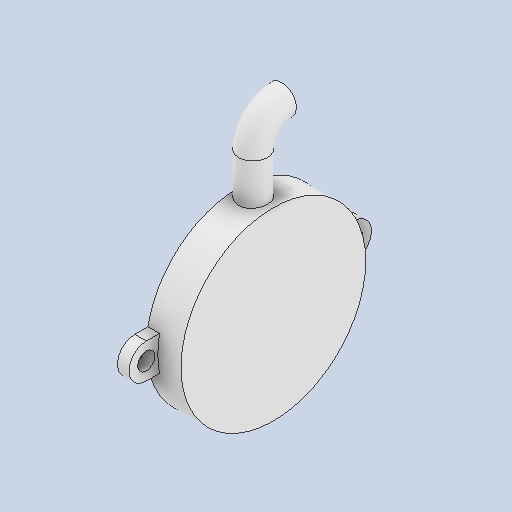
# Autodesk Inventor part: cylinder_head
Saved by Autodesk Inventor 2026.1 (Build 301233020, 233B)
## iProperties
Created: 2025-12-09
Part Number: cylinder_head
Material: Plastica ABS
Document SubType Name: Modeling
Designer: maxbu
Density: 1.06 g/cm^3
Appearance: Liscia - Bianco
Mass: 1.64306 g
Surface Area: 32.0135 cm^2
Volume: 1.55006 cm^3
Author: maxbu
Autodesk Inventor part; units mm, degrees
sketch "Schizzo1" plane through (0, 0, 0) normal (1, 0, 0) x (0, 1, 0)
  circle A0 centre (0, 0) radius 16
  circle A1 centre (0, 0) radius 15
  dimension "d0" = 32
  dimension "d1" = 30
  constraints: 2 centre point, 2 coincident
  measures "d0" diameter of A0
  measures "d1" diameter of A1
extrude "Estrusione1" add sketch "Schizzo1" along normal blind 5
sketch "Schizzo2" plane through (0, 0, 0) normal (1, 0, 0) x (0, 1, 0)
  circle A0 centre (0, -18) radius 1.5
  arc A1 (-3, -18) -> (3, -18) centre (0, -18) ccw
  line L0 (3, -18) -> (3, -15.7162)
  line L1 (-3, -18) -> (-3, -15.7162)
  circle A2 centre (0, 0) radius 16 projected
  line L2 (0, -18) -> (0, 0) construction
  line L3 (0, 0) -> (16, 0) construction
  circle A3 centre (0, 18) radius 1.5
  arc A4 (3, 18) -> (-3, 18) centre (0, 18) ccw
  line L4 (3, 18) -> (3, 15.7162)
  line L5 (-3, 18) -> (-3, 15.7162)
  dimension "d4" = 3
  dimension "d5" = 3
  dimension "d32" = 18
  constraints: 12 end point, 7 point on circle, 6 symmetric about line, 4 centre point, 3 coincident, 3 vertical, 2 tangent, 1 horizontal, 2 other
  measures "d4" radius of A1
  measures "d5" diameter of A0
  measures "d32" distance of point (0, 0) A0.centre
extrude "Estrusione2" add sketch "Schizzo2" along normal blind 2 contours L1 A2 L0 A1 | L5 A4 L4 A2
sketch "Schizzo5" plane through (5, 0, 0) normal (1, 0, 0) x (0, 0, -1)
  circle A0 centre (0, 0) radius 16 projected
extrude "Estrusione4" add sketch "Schizzo5" along normal blind 1
ref_plane "Piano di lavoro1" through (0, 20, 0) normal (0, 1, 0) x (-1, 0, 0)
sketch "Schizzo6" plane through (0, 20, 0) normal (0, 1, 0) x (-1, 0, 0)
  line L0 (0, 15.7162) -> (0, -15.7162) projected
  circle A0 centre (-2.5, 0) radius 2.5
  line L1 (-5, -15) -> (-5, 15) projected
  line L2 (0, 0) -> (-2.5, 0) construction
  line L3 (-2.5, 0) -> (-5, 0) construction
  dimension "d22" = 5
  constraints: 4 end point, 1 centre point, 1 collinear, 1 horizontal, 1 midpoint
  measures "d22" diameter of A0
extrude "Estrusione5" add sketch "Schizzo6" against normal up to surface round surface about axis through (0, 0, 0) along (1, 0, 0) radius 16 far side no
sketch "Schizzo7" plane through (2.5, 20, 0) normal (0, 1, 0) x (1, 0, 0)
  circle A0 centre (0, 0) radius 2.5 projected
  point P0 (-2.5, 0)
  constraints: 1 coincident, 1 horizontal alignment
hole "Foro1" at (2.5, 20, 0) direction (0, -1, 0) diameter 3 depth 8 tip angle 118
ref_plane "Work Plane3" through (0, 0, -5) normal (0, 0, 1) x (1, 0, 0)
sketch "Sketch10" plane through (0, 0, -5) normal (0, 0, 1) x (1, 0, 0)
  line L0 (5, 20) -> (0, 20) construction
  line L1 (2.5, 20) -> (2.5, 36) construction
  circle A0 centre (2.5, 28) radius 2.5
  line L2 (-1.202, 0) -> (7.2003, 0) projected
  circle A1 centre (2.5, 28) radius 1.5
  point P0 (0, 0)
  dimension "d43" = 5
  dimension "d44" = 28
  dimension "d53" = 3
  constraints: 2 centre point, 2 end point, 2 midpoint, 1 coincident, 1 vertical
  measures "d43" diameter of A0
  measures "d44" distance from line of A0.centre L2
  measures "d53" diameter of A1
ref_plane "Work Plane4" through (2.5, 0, 0) normal (1, 0, 0) x (0, 1, 0)
sketch "Sketch11" plane through (2.5, 0, 0) normal (1, 0, 0) x (0, 1, 0)
  line L0 (-26, 0) -> (44, 0) projected
  line L1 (28, -5) -> (28, -5)
  line L2 (23, 0) -> (20, 0)
  line L3 (20, -2.5) -> (20, 2.5) projected
  arc A0 (28, -5) -> (23, 0) centre (23, -5) ccw
  point P0 (0, 0)
  point P1 (28, 0)
  dimension "d50" = 5
  constraints: 4 end point, 3 point on line, 2 point on circle, 2 tangent, 1 centre point, 1 midpoint, 1 perpendicular
  measures "d50" radius of A0
sweep "Sweep1" add profiles "Sketch10" path "Sketch11" path curves L1 A0 L2
